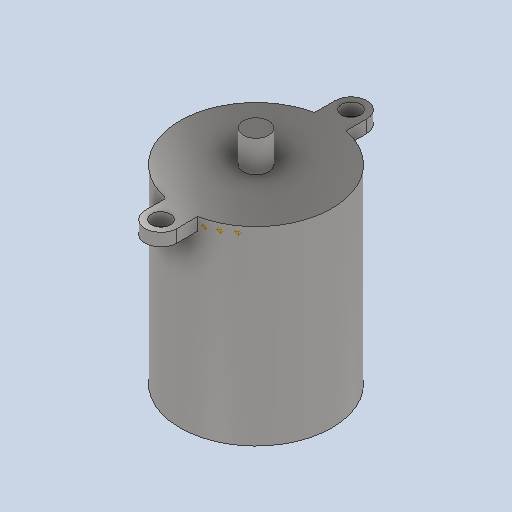
# Autodesk Inventor part: motor
Saved by Autodesk Inventor 2026.1 (Build 301233020, 233B)
## iProperties
Created: 2025-11-26
Part Number: motor
Material: Acciaio, Carbonio
Document SubType Name: Modeling
Designer: maxbu
Density: 7.85 g/cm^3
Appearance: Semilucidato
Mass: 107.602 g
Surface Area: 33.7737 cm^2
Volume: 13.7073 cm^3
Categories: <MemberInstance><Categories><Category DisplayName="" Mnemonic="CABLEANDHARNESS" InternalName="e4a7e005-5e42-4d16-b293-125e7f0d0512"><Category DisplayName="" Mnemonic="CONNECTORS" InternalName="6f634eba-a678-4820-a31d-2c2d5ee6728e"><CategoryParameter DisplayName="" Mnemonic="REFDES" InternalName="c3740e8c-60ab-4d5d-8584-52b73222f2f0"/><Category DisplayName="" Mnemonic="DISCRETEWIRE" InternalName="9a3407de-09b2-4cdb-8c40-9708d5144a28"/></Category></Category></Categories><FamilyTemplate><FamilyTemplateParameters></FamilyTemplateParameters></FamilyTemplate><CategoryParameterMap><ParamToTemplateMap><ParamToTemplate CategoryParameter="//CategoryParameter[@InternalName='c3740e8c-60ab-4d5d-8584-52b73222f2f0']" ConstantValue=""/></ParamToTemplateMap></CategoryParameterMap></MemberInstance>
Author: maxbu
Autodesk Inventor part; units mm, degrees
ref_plane "YZ Plane" through (0, 0, 0) normal (1, 0, 0) x (0, 1, 0)
ref_plane "XZ Plane" through (0, 0, 0) normal (0, 1, 0) x (-1, 0, 0)
sketch "Schizzo1" plane through (0, 0, 0) normal (0, 0, 1) x (1, 0, 0)
  line L0 (0, 0) -> (12, 0)
  line L1 (12, 0) -> (12, 30)
  line L2 (12, 30) -> (2, 30)
  line L3 (2, 30) -> (2, 35)
  line L4 (2, 35) -> (0, 35)
  line L5 (0, 0) -> (0, 35)
  dimension "d0" = 2
  dimension "d2" = 30
  dimension "d3" = 5
  dimension "d21" = 12
  constraints: 12 end point, 3 perpendicular, 1 horizontal, 1 parallel, 1 vertical
  measures "d0" distance of L3.end L4.end
  measures "d2" distance of L0.end L1.end
  measures "d3" distance of L2.end L3.end
  measures "d21" distance of L0.start L0.end
revolve "Rivoluzione1" add sketch "Schizzo1" angle 360 about axis through (0, 0, 0) along (0, 1, 0)
sketch "Schizzo2" plane through (0, 0, 0) normal (0, 0, 1) x (1, 0, 0)
  circle A0 centre (15, 15) radius 1
  line L0 (12, 0) -> (12, 30) projected
  line L1 (12, 15) -> (15, 15) construction
  arc A1 (15, 13) -> (15, 17) centre (15, 15) ccw
  line L2 (15, 17) -> (12, 17)
  line L3 (15, 13) -> (12, 13)
  point P0 (0, 0)
  dimension "d5" = 2
  dimension "d6" = 4
  dimension "d7" = 3
  constraints: 6 end point, 2 centre point, 2 perpendicular, 2 point on circle, 2 point on line, 2 tangent, 1 coincident, 1 horizontal, 1 midpoint
  measures "d5" diameter of A0
  measures "d6" diameter of A1
  measures "d7" distance from line of L0 L1.end
extrude "Estrusione1" [suppressed]
mirror "Speculare1" [suppressed]
sketch "Schizzo3" plane through (0, 35, 0) normal (0, 1, 0) x (1, 0, 0)
  circle A0 centre (0, 0) radius 2 projected
  circle A1 centre (0, 0) radius 4
  line L0 (-1, 3.873) -> (-0.2, 3.073)
  line L1 (0.2, 3.073) -> (1, 3.873)
  line L2 (0, 0) -> (0, 2.873) construction
  line L3 (-0.2, 3.073) -> (0.2, 3.073)
  line L4 (0, 2.873) -> (-0.2, 3.073) construction
  line L5 (0, 2.873) -> (0.2, 3.073) construction
  line L6 (-1.6445, 2.6037) -> (-1.4675, 3.7211)
  line L7 (-1.9681, 2.3685) -> (-1.6445, 2.6037)
  line L8 (-3.0855, 2.5455) -> (-1.9681, 2.3685)
  line L9 (-2.8608, 1.1398) -> (-3.3744, 2.1479)
  line L10 (-2.9844, 0.7594) -> (-2.8608, 1.1398)
  line L11 (-3.9924, 0.2458) -> (-2.9844, 0.7594)
  line L12 (-2.9844, -0.7594) -> (-3.9924, -0.2458)
  line L13 (-2.8608, -1.1398) -> (-2.9844, -0.7594)
  line L14 (-3.3744, -2.1479) -> (-2.8608, -1.1398)
  line L15 (-1.9681, -2.3685) -> (-3.0855, -2.5455)
  line L16 (-1.6445, -2.6037) -> (-1.9681, -2.3685)
  line L17 (-1.4675, -3.7211) -> (-1.6445, -2.6037)
  line L18 (-0.2, -3.073) -> (-1, -3.873)
  line L19 (0.2, -3.073) -> (-0.2, -3.073)
  line L20 (1, -3.873) -> (0.2, -3.073)
  line L21 (1.6445, -2.6037) -> (1.4675, -3.7211)
  line L22 (1.9681, -2.3685) -> (1.6445, -2.6037)
  line L23 (3.0855, -2.5455) -> (1.9681, -2.3685)
  line L24 (2.8608, -1.1398) -> (3.3744, -2.1479)
  line L25 (2.9844, -0.7594) -> (2.8608, -1.1398)
  line L26 (3.9924, -0.2458) -> (2.9844, -0.7594)
  line L27 (2.9844, 0.7594) -> (3.9924, 0.2458)
  line L28 (2.8608, 1.1398) -> (2.9844, 0.7594)
  line L29 (3.3744, 2.1479) -> (2.8608, 1.1398)
  line L30 (1.9681, 2.3685) -> (3.0855, 2.5455)
  line L31 (1.6445, 2.6037) -> (1.9681, 2.3685)
  line L32 (1.4675, 3.7211) -> (1.6445, 2.6037)
  dimension "d10" = 1
  dimension "d11" = 1
  dimension "d12" = 0.4
  dimension "d13" = 45
  dimension "d14" = 8
  dimension "d17" = 360
  constraints: 66 end point, 2 collinear, 2 point on circle, 1 centre point, 1 coincident, 1 horizontal, 1 vertical, 71 other
  measures "d10" horizontal distance of L2.end L1.end
  measures "d11" horizontal distance of L1.end L2.end
  measures "d12" distance of L1.start L0.end
  measures "d13" angle of L0 L2
  measures "d14" diameter of A1
extrude "Estrusione2" add sketch "Schizzo3" along normal blind 4 contours A0 | A1 L26 L25 L24 L23 L22 L21 L20 L19 L18 L17 L16 L15 L14 L13 L12 L11 L10 L9 L8 L7 L6 L0 L3 L1 L32 L31 L30 L29 L28 L27
sketch "Schizzo4" plane through (0, 30, 0) normal (0, 1, 0) x (1, 0, 0)
  arc A0 (2.5, 15) -> (-2.5, 15) centre (0, 15) ccw
  circle A1 centre (0, 15) radius 1.5
  line L0 (-2.5, 15) -> (-2.5, 11.7367)
  circle A2 centre (0, 0) radius 12 projected
  line L1 (2.5, 15) -> (2.5, 11.7367)
  circle A3 centre (0, 0) radius 2 projected
  line L2 (0, 0) -> (0, 15) construction
  dimension "d22" = 3
  dimension "d23" = 5
  dimension "d27" = 15
  constraints: 6 end point, 4 point on circle, 3 vertical, 2 centre point, 2 tangent, 1 coincident
  measures "d22" diameter of A1
  measures "d23" diameter of A0
  measures "d27" distance of point (0, 0) A0.centre
extrude "Estrusione3" add sketch "Schizzo4" against normal blind 2 contours L1 A2 L0 A0
mirror "Speculare2" about plane through (0, 0, 0) normal (0, 0, 1) of "Estrusione3"
ref_plane "Piano di lavoro1" through (0, 35, 0) normal (0, -1, 0) x (1, 0, 0)
split "Divisione1" plane through (0, 35, 0) removes the side toward (0, 1, 0)
